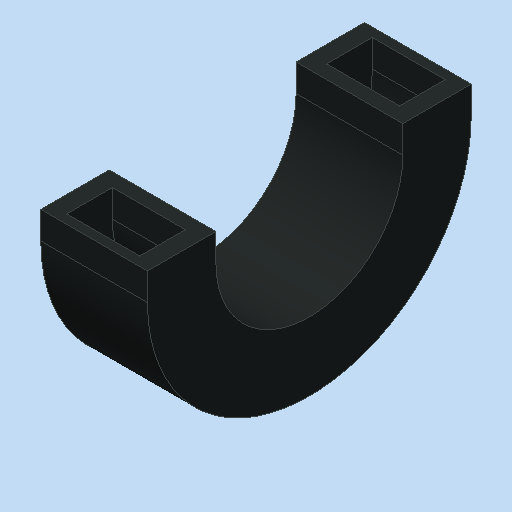
# Autodesk Inventor part: MM0868AN100_G80_509
Saved by Autodesk Inventor 2023.3 (Build 273359000, 359)
## iProperties
Part Number: MM0868AN100_G80_509
Material: Generisch
Description: =<RBPARTNOTITLE2>
Document SubType Name: Modeling
Designer: Rose
Density: 1 g/cm^3
Appearance: Grau-S
Mass: 18.8419 g
Surface Area: 133.391 cm^2
Volume: 18.8419 cm^3
RBDOCUMENTTYPE: DRF
RBDOCUMENTVERSION: 00
RBDRAWINGMAINSCALE: 1:1
RBDRAWINGMISSINGSPEC: --
RBDRAWINGVOLUME: --
RBGBEDGESIN1: +0,5
RBGBEDGESIN2: +0,2
RBGBEDGESOUT1: -0,3
RBGBEDGESOUT2: -0,1
RBMATERIAL: --
RBMATMEETS: --
RBMATNO: =<Part Number>
RBPARTMADEOF: 5 Glieder = 100mm
RBPARTNO: SIEHE MNR
RBPARTNOTITLE1: manufactured part
RBPARTNOTITLE2: Anfertigungsteil
RBPARTSAFETYINDICATOR: --
RBSURFACE: --
RBSURFACE2: --
RBZEDGESNORM: ISO13715:2002-06
RBZGENDIMCLASS: m
RBZGENDIMNORM: ISO 2768-1:1989-11
RBZGENGEOCLASS: H
RBZGENGEONORM: ISO 2768-2:1989-11
RBZSURFACENORM: ISO13D2:2002-02
RBZTOLERANCENORM: ISO 14405-1:2010-12
AnP_Material: =<Material>
AnP_TemplVers: 20190222
AnP_Kategorie: 1
Author: Rose
Keywords: =<RBPARTMADEOF>
Comments: =<RBSURFACE2>
Revision Number: 01
Autodesk Inventor part; units mm, degrees
ref_plane "YZ Plane" through (0, 0, 0) normal (1, 0, 0) x (0, 1, 0)
ref_plane "XZ Plane" through (0, 0, 0) normal (0, 1, 0) x (-1, 0, 0)
ref_plane "XY Plane" through (0, 0, 0) normal (0, 0, 1) x (1, 0, 0)
sketch "Skizze1" plane through (0, 0, 0) normal (0, 0, 1) x (1, 0, 0)
  line L0 (0, 38.5) -> (0, 17.5) projected
  line L1 (-16.38, 0) -> (16.38, 0) projected
  line L2 (-11.7, 35.5) -> (11.7, 35.5)
  line L3 (11.7, 35.5) -> (11.7, 20.5)
  line L4 (11.7, 20.5) -> (-11.7, 20.5)
  line L5 (-11.7, 20.5) -> (-11.7, 35.5)
  line L6 (-8, 33.5) -> (8, 33.5)
  line L7 (8, 33.5) -> (8, 23.5)
  line L8 (8, 23.5) -> (-8, 23.5)
  line L9 (-8, 23.5) -> (-8, 33.5)
  line L10 (-11.7, 28) -> (11.7, 28) construction
  dimension "d0" = 23.4
  dimension "d1" = 15
  dimension "d3" = 16
  dimension "d4" = 10
  dimension "d5" = 3
  dimension "d7" = 28
  constraints: 18 end point, 4 parallel, 3 perpendicular, 2 horizontal, 2 midpoint, 2 other
  measures "d0" distance between parallel lines of L3 L5
  measures "d1" distance between parallel lines of L4 L2
  measures "d3" distance between parallel lines of L9 L7
  measures "d4" distance between parallel lines of L8 L6
  measures "d5" distance between parallel lines of L4 L8
  measures "d7" distance between parallel lines of L10 L1
revolve "Umdrehung1" add sketch "Skizze1" angle 180 about axis through (0, 0, 0) along (-1, 0, 0) contours L2 L3 L4 L0 L8 L7 L6 | L0 L6 L9 L8 L4 L5 L2
sketch "Skizze2" plane through (-11.7, 35.5, 0) normal (0, 0, 1) x (1, 0, 0)
  line L0 (3.7, -12) -> (3.7, -2) projected
  line L1 (3.7, -2) -> (19.7, -2) projected
  line L2 (19.7, -2) -> (19.7, -12) projected
  line L3 (19.7, -12) -> (3.7, -12) projected
  line L4 (0, 0) -> (23.4, 0) projected
  line L5 (0, -15) -> (0, 0) projected
  line L6 (23.4, -15) -> (0, -15) projected
  line L7 (23.4, 0) -> (23.4, -15) projected
  line L8 (3.7, -69) -> (3.7, -59) projected
  line L9 (3.7, -59) -> (19.7, -59) projected
  line L10 (19.7, -59) -> (19.7, -69) projected
  line L11 (19.7, -69) -> (3.7, -69) projected
  line L12 (0, -71) -> (23.4, -71) projected
  line L13 (23.4, -71) -> (23.4, -56) projected
  line L14 (23.4, -56) -> (0, -56) projected
  line L15 (0, -56) -> (0, -71) projected
extrude "Extrusion1" add sketch "Skizze2" along normal blind 6
